ScreenTop (Autodesk Fusion 360 design; units mm, degrees)
Autodesk Fusion 360 part; units mm, degrees
sketch "Sketch1" plane through (0, 0, 0) normal (0, 1, 0) x (1, 0, 0)
  line L0 (62.75, -41.25) -> (-62.75, -41.25)
  line L1 (-62.75, -41.25) -> (-62.75, 41.25)
  line L2 (-62.75, 41.25) -> (62.75, 41.25)
  line L3 (62.75, 41.25) -> (62.75, -41.25)
  line L4 (60.75, -39.25) -> (-60.75, -39.25)
  line L5 (-60.75, -39.25) -> (-60.75, 39.25)
  line L6 (-60.75, 39.25) -> (60.75, 39.25)
  line L7 (60.75, 39.25) -> (60.75, -39.25)
  line L8 (0, 32.25) -> (-57.75, 32.25)
  line L9 (57.45, 0) -> (57.45, 32.25)
  line L10 (-57.75, 32.25) -> (57.45, 32.25)
  line L11 (57.45, 32.25) -> (57.45, -36.25)
  line L12 (57.45, -36.25) -> (-57.75, -36.25)
  line L13 (-57.75, -36.25) -> (-57.75, 32.25)
  constraint perpendicular L0 L1
  constraint parallel L0 L2
  constraint parallel L1 L3
  constraint horizontal L0
  constraint perpendicular L4 L5
  constraint parallel L4 L6
  constraint parallel L5 L7
  constraint horizontal L4
  constraint horizontal L10
  constraint vertical L11
  constraint horizontal L12
  constraint vertical L13
extrude "Extrude1" add sketch "Sketch1" along normal blind 2 contours L0 L1 L2 L3 | L4 L5 L6 L7 | L8 L9 L10 L11 L12 L13
extrude "Extrude2" add sketch "Sketch1" along normal blind 3 contours L0 L1 L2 L3
extrude "Extrude3" cut sketch "Sketch1" along normal blind 5 contours L8 L9 L10 L11 L12 L13
sketch "Sketch2" plane through (0, 3, 0) normal (0, 1, 0) x (-1, 0, 0)
  line L0 (60.75, -39.25) -> (-60.75, -39.25)
  line L1 (-60.75, -39.25) -> (-60.75, 39.25)
  line L2 (-60.75, 39.25) -> (60.75, 39.25)
  line L3 (60.75, 39.25) -> (60.75, -39.25)
  line L4 (-62.75, -41.25) -> (62.75, -41.25)
  line L5 (62.75, -41.25) -> (62.75, 41.25)
  line L6 (62.75, 41.25) -> (-62.75, 41.25)
  line L7 (-62.75, 41.25) -> (-62.75, -41.25)
  line L8 (-62.75, 32.4878) -> (-61.75, 32.4878)
  line L9 (-55.7262, 41.25) -> (-55.7262, 40.25)
  line L10 (-61.75, 32.4878) -> (-61.75, 40.25)
  line L11 (-55.7262, 40.25) -> (-61.75, 40.25)
  line L12 (56.3945, -40.25) -> (61.75, -40.25)
  line L13 (61.75, -34.8708) -> (61.75, -40.25)
  line L14 (-61.75, 40.25) -> (61.75, 40.25)
  line L15 (61.75, 40.25) -> (61.75, -40.25)
  line L16 (61.75, -40.25) -> (-61.75, -40.25)
  line L17 (-61.75, -40.25) -> (-61.75, 40.25)
  dimension "d15" = 1
  dimension "d16" = 1
  constraint coincident L7 L8.start
  constraint coincident L6 L9.start
  constraint perpendicular L10 L11
  constraint perpendicular L12 L13
  constraint horizontal L14
  constraint vertical L15
  constraint horizontal L16
  constraint vertical L17
  measures "d15" distance of L8.start L8.end
  measures "d16" distance of L9.start L9.end
extrude "Extrude4" cut sketch "Sketch2" against normal blind 1 contours L10 L11 L12 L13 L14 L15 L16 L17
